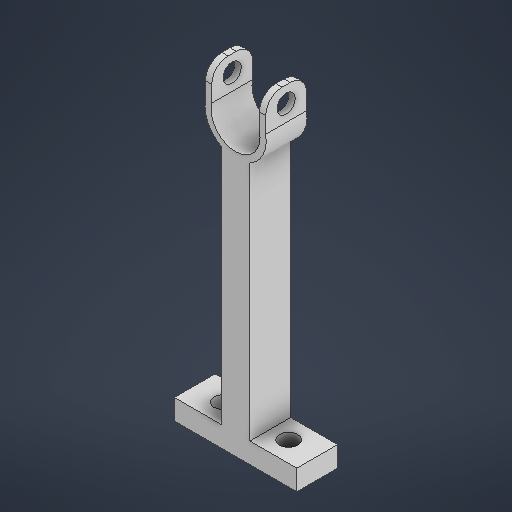
# Autodesk Inventor part: support_de_maintient_horizontal_tuyau
Saved by Autodesk Inventor 2026 (Build 300175000, 175)
## iProperties
Created: 2025-05-04
Part Number: support_de_maintient_horizontal_tuyau
Material: Générique
Document SubType Name: Modeling
Designer: virgi
Density: 1 g/cm^3
Appearance: Par défaut
Author: virgi
Autodesk Inventor part; units mm, degrees
ref_plane "YZ Plane" through (0, 0, 0) normal (1, 0, 0) x (0, 1, 0)
sketch "Esquisse1" plane through (0, 0, 0) normal (0, 0, 1) x (1, 0, 0)
  line L0 (-15, 0) -> (-15, 5)
  line L1 (-15, 5) -> (-3.5, 5)
  line L2 (-15, 0) -> (0, 0)
  line L3 (0, 153.7683) -> (0, -12.5018)
  line L4 (-3.5, 5) -> (-3.5, 64)
  arc A0 (-7.3744, 72) -> (-3.5, 64) centre (0, 70.6332) ccw
  arc A1 (-5.8423, 72) -> (0, 64.6332) centre (0, 70.6332) ccw
  line L5 (-5.8423, 72) -> (-7.3744, 72)
  line L6 (-7.3744, 72) -> (-7.3744, 80)
  line L7 (-7.3744, 80) -> (-5.8423, 80)
  line L8 (-5.8423, 80) -> (-5.8423, 72)
  line L9 (15, 0) -> (15, 5)
  line L10 (15, 5) -> (3.5, 5)
  line L11 (15, 0) -> (0, 0)
  line L12 (3.5, 5) -> (3.5, 64)
  arc A2 (3.5, 64) -> (7.3744, 72) centre (0, 70.6332) ccw
  arc A3 (0, 64.6332) -> (5.8423, 72) centre (0, 70.6332) ccw
  line L13 (5.8423, 72) -> (7.3744, 72)
  line L14 (7.3744, 72) -> (7.3744, 80)
  line L15 (7.3744, 80) -> (5.8423, 80)
  line L16 (5.8423, 80) -> (5.8423, 72)
  point P0 (-6.6083, 72)
  point P1 (6.6083, 72)
  dimension "d0" = 5
  dimension "d1" = 15
  dimension "d5" = 7
  dimension "d6" = 1.5
  dimension "d8" = 6
  dimension "d9" = 8
  dimension "d11" = 8
  dimension "d12" = 80
  constraints: 34 end point, 9 symmetric about line, 8 point on circle, 4 centre point, 4 vertical, 3 coincident, 3 perpendicular, 2 horizontal, 2 midpoint, 2 point on line, 2 other
  measures "d0" distance of L0.start L0.end
  measures "d1" distance from line of L2.end L0
  measures "d5" diameter of L4 L3
  measures "d6" radial gap between concentric circles of A0 A1
  measures "d8" radius of A1
  measures "d9" distance from line of L4.end L5
  measures "d11" distance between parallel lines of L7 L5
  measures "d12" distance between parallel lines of L2 L7
extrude "Extrusion1" add sketch "Esquisse1" along normal blind 10
sketch "Esquisse2" plane through (-7.3744, 72, 0) normal (-1, 0, 0) x (0, 0, 1)
  line L0 (0, 0) -> (10, 0) projected
  line L1 (0, 8) -> (0, 0) projected
  point P0 (0, -72)
  point P1 (5, 4)
  dimension "d22" = 4
  dimension "d23" = 5
  measures "d22" distance from line of L0 point (5, 4)
  measures "d23" distance from line of L1 point (5, 4)
hole "Perçage1" at (-7.3744, 76, 5) direction (1, 0, 0) diameter 4.5 end through all
fillet "Congé1" radius 4 4 edges at (6.6083, 80, 10) (6.6083, 80, 0) (-6.6083, 80, 10) (-6.6083, 80, 0)
ref_plane "Plan de construction2" through (0, 5, 0) normal (-1, 0, 0) x (0, 0, 1)
ref_plane "Plan de construction3" through (0, 0, 5) normal (0, 0, 1) x (1, 0, 0)
sketch "Esquisse4" plane through (-15, 0, 0) normal (0, -1, 0) x (1, 0, 0)
  line L0 (15, -2) -> (15, 12) projected
  line L1 (-6, 5) -> (36, 5) projected
  point P0 (15, 0)
  point P1 (7, 5)
  point P2 (23, 5)
  dimension "d40" = 8
  constraints: 1 point on line, 1 symmetric about line
  measures "d40" distance from line of L0 point (7, 5)
hole "Perçage3" at (-8, 0, 5) at (8, 0, 5) direction (0, 1, 0) diameter 4.5 depth 8 tip angle 118
